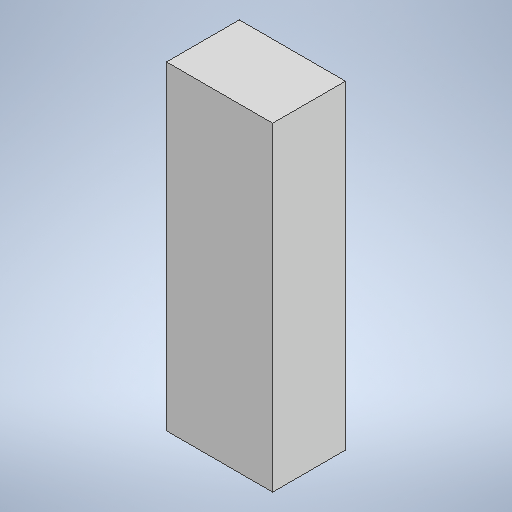
# Autodesk Inventor part: iLogicTest
Saved by Autodesk Inventor 2027.2 (Build 312334000, 334)
## iProperties
Created: 2026-11-24
Part Number: iLogicTest
Material: Generisch
Document SubType Name: Modeling
Designer: twiesendanger
Density: 1 g/cm^3
Appearance: Vorgabe
RuleStatus: InUse
Author: twiesendanger
Masse: 0 kg
Fläche: 0
Volumen: 0
Abmasse: 0 mm x 0 mm x 0 mm
Autodesk Inventor part; units mm, degrees
ref_plane "YZ Plane" through (0, 0, 0) normal (1, 0, 0) x (0, 1, 0)
ref_plane "XZ Plane" through (0, 0, 0) normal (0, 1, 0) x (-1, 0, 0)
ref_plane "XY Plane" through (0, 0, 0) normal (0, 0, 1) x (1, 0, 0)
sketch "Sketch1" plane through (0, 0, 0) normal (0, 1, 0) x (-1, 0, 0)
  line L0 (6.299, 19.257) -> (-8.2787, 19.257)
  line L1 (-8.2787, 19.257) -> (-8.2787, -24.6202)
  line L2 (-8.2787, -24.6202) -> (6.299, -24.6202)
  line L3 (6.299, -24.6202) -> (6.299, 19.257)
  point P0 (0, 0)
  constraints: 8 end point, 2 parallel, 1 horizontal, 1 perpendicular
extrude "Extrusion1" add sketch "Sketch1" along normal blind 10
body "Solid1"
